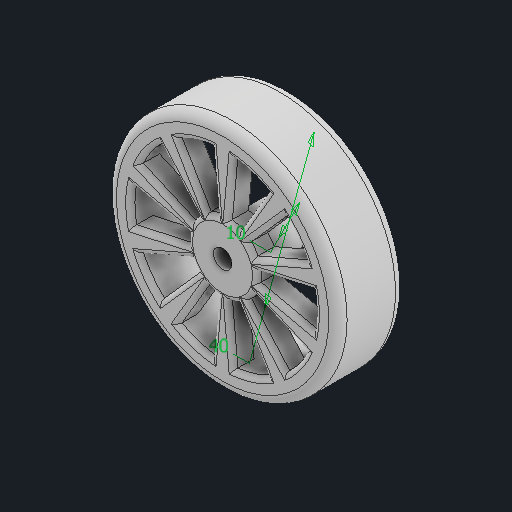
# Autodesk Inventor part: roues_3d_moteur_axe_petit_robot
Saved by Autodesk Inventor 2026 (Build 300175050, 175E)
## iProperties
Created: 2025-05-23
Part Number: roues_3d_moteur_axe_petit_robot
Material: Generisch
Document SubType Name: Modeling
Designer: karle
Density: 1 g/cm^3
Appearance: Vorgabe
Author: karle
Autodesk Inventor part; units mm, degrees
ref_plane "YZ Plane" through (0, 0, 0) normal (1, 0, 0) x (0, 1, 0)
sketch "Skizze1" plane through (0, 0, 0) normal (0, 0, 1) x (1, 0, 0)
  circle A0 centre (0, 0) radius 2
  circle A1 centre (0, 0) radius 25
  dimension "d0" = 4
  dimension "d1" = 50
  constraints: 2 centre point, 2 coincident
  measures "d0" diameter of A0
  measures "d1" diameter of A1
extrude "Extrusion1" add sketch "Skizze1" along normal mid plane 14.5
sketch "Skizze2" plane through (0, 0, -7.25) normal (0, 0, -1) x (-1, 0, 0)
  circle A0 centre (0, 0) radius 20
  circle A1 centre (0, 0) radius 5
  dimension "d4" = 10
  dimension "d5" = 40
  constraints: 2 centre point, 2 coincident
  measures "d4" diameter of A1
  measures "d5" diameter of A0
extrude "Extrusion2" cut sketch "Skizze2" against normal blind 10
sketch "Skizze3" plane through (0, 0, 7.25) normal (0, 0, 1) x (1, 0, 0)
  circle A0 centre (0, 0) radius 2 projected
  arc A1 (-7.4013, 1.213) -> (-7.4013, -1.213) centre (0, 0) ccw
  arc A2 (-19.6121, 3.92) -> (-19.6121, -3.92) centre (0, 0) ccw
  line L0 (-19.6121, 3.92) -> (-7.4013, 1.213)
  line L1 (-7.4013, -1.213) -> (-19.6121, -3.92)
  line L2 (0, 0) -> (-34.8454, 0)
  dimension "d8" = 40
  dimension "d9" = 15
  dimension "d12" = 25
  constraints: 6 end point, 4 point on circle, 2 centre point, 2 coincident, 1 horizontal, 1 other
  measures "d8" diameter of A2
  measures "d9" diameter of A1
  measures "d12" angle of L0 L1
extrude "Extrusion3" cut sketch "Skizze3" against normal blind 5 contours A1 L2 A2 L0 | A1 L1 A2 L2
pattern_circular "Runde Anordnung1" count 10 over 360 about axis through (0, 0, -10) along (0, 0, 1) of "Extrusion3"
fillet "Rundung1" radius 1 40 edges at (-13.5067, 2.5665, 7.25) (-20, 0, 7.25) (-13.5067, -2.5665, 7.25) (-7.5, 0, 7.25) (-12.4357, 5.8627, 7.25) (-16.1803, 11.7557, 7.25) (-9.4186, 10.0154, 7.25) (-6.0676, 4.4084, 7.25) (-2.3176, 7.1329, 7.25) (-6.6147, 12.0525, 7.25) (-6.1803, 19.0211, 7.25) (-1.7329, 13.6387, 7.25) (1.7329, 13.6387, 7.25) (6.1803, 19.0211, 7.25) (6.6147, 12.0525, 7.25) (2.3176, 7.1329, 7.25) (9.4186, 10.0154, 7.25) (12.4357, 5.8627, 7.25) (6.0676, 4.4084, 7.25) (16.1803, 11.7557, 7.25) (20, 0, 7.25) (16.1803, -11.7557, 7.25) (12.4357, -5.8627, 7.25) (13.5067, -2.5665, 7.25) (13.5067, 2.5665, 7.25) (7.5, 0, 7.25) (6.0676, -4.4084, 7.25) (9.4186, -10.0154, 7.25) (6.6147, -12.0525, 7.25) (2.3176, -7.1329, 7.25) (1.7329, -13.6387, 7.25) (6.1803, -19.0211, 7.25) (-1.7329, -13.6387, 7.25) (-6.1803, -19.0211, 7.25) (-6.6147, -12.0525, 7.25) (-2.3176, -7.1329, 7.25) (-9.4186, -10.0154, 7.25) (-12.4357, -5.8627, 7.25) (-6.0676, -4.4084, 7.25) (-16.1803, -11.7557, 7.25)
sketch "Skizze4" plane through (0, 0, -7.25) normal (0, 0, -1) x (-1, 0, 0)
  circle A0 centre (0, 0) radius 7.5
  circle A1 centre (0, 0) radius 2
  dimension "d40" = 4
  dimension "d41" = 15
  constraints: 2 centre point, 2 coincident
  measures "d40" diameter of A1
  measures "d41" diameter of A0
extrude "Extrusion4" cut sketch "Skizze4" against normal blind 2
ref_plane "Arbeitsebene1" through (0, 5, -7.25) normal (0, 1, 0) x (-1, 0, 0)
ref_plane "Arbeitsebene2" through (0, 2, 0) normal (0, 1, 0) x (-1, 0, 0)
fillet "Rundung3" radius 2 2 edges at (-25, 0, 7.25) (-25, 0, -7.25)
